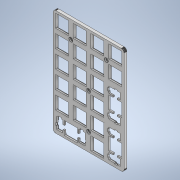
# Autodesk Inventor part: Numpad plate v1
Saved by Autodesk Inventor 2022.5 (Build 265521000, 521)
## iProperties
Created: 2024-05-07
Part Number: Numpad plate v1
Material: Generic
Document SubType Name: Modeling
Designer: OsterhaudtM
Density: 1 g/cm^3
Appearance: Default
Autodesk Inventor part; units mm, degrees
(part 1 of 2)
ref_plane "YZ Plane" through (0, 0, 0) normal (1, 0, 0) x (0, 1, 0)
ref_plane "XZ Plane" through (0, 0, 0) normal (0, 1, 0) x (-1, 0, 0)
ref_plane "XY Plane" through (0, 0, 0) normal (0, 0, 1) x (1, 0, 0)
sketch "Sketch1" plane through (0, 0, 0) normal (0, 0, 1) x (1, 0, 0)
  point P0 (0, 0)
sketch "0" plane through (0, 0, 0) normal (0, 0, 1) x (1, 0, 0)
  line L0 (73.2966, 114.558) -> (73.5323, 114.548)
  line L1 (73.5323, 114.548) -> (73.7651, 114.522)
  line L2 (73.7651, 114.522) -> (73.9965, 114.475)
  line L3 (73.9965, 114.475) -> (74.2237, 114.411)
  line L4 (74.2237, 114.411) -> (74.4442, 114.329)
  line L5 (74.4442, 114.329) -> (74.658, 114.231)
  line L6 (74.658, 114.231) -> (74.8633, 114.115)
  line L7 (74.8633, 114.115) -> (75.0591, 113.986)
  line L8 (75.0591, 113.986) -> (75.245, 113.84)
  line L9 (75.245, 113.84) -> (75.4172, 113.68)
  line L10 (75.4172, 113.68) -> (75.577, 113.506)
  line L11 (75.577, 113.506) -> (75.723, 113.322)
  line L12 (75.723, 113.322) -> (75.8543, 113.126)
  line L13 (75.8543, 113.126) -> (75.97, 112.919)
  line L14 (75.97, 112.919) -> (76.0677, 112.705)
  line L15 (76.0677, 112.705) -> (76.1488, 112.485)
  line L16 (76.1488, 112.485) -> (76.2138, 112.258)
  line L17 (76.2138, 112.258) -> (76.2593, 112.028)
  line L18 (76.2593, 112.028) -> (76.2868, 111.794)
  line L19 (76.2868, 111.794) -> (76.2963, 111.558)
  line L20 (76.2963, 111.558) -> (76.2963, 3.2563)
  line L21 (76.2963, 3.2563) -> (76.2868, 3.0207)
  line L22 (76.2868, 3.0207) -> (76.2593, 2.7878)
  line L23 (76.2593, 2.7878) -> (76.2138, 2.5563)
  line L24 (76.2138, 2.5563) -> (76.1488, 2.3289)
  line L25 (76.1488, 2.3289) -> (76.0677, 2.1084)
  line L26 (76.0677, 2.1084) -> (75.97, 1.8948)
  line L27 (75.97, 1.8948) -> (75.8543, 1.6895)
  line L28 (75.8543, 1.6895) -> (75.723, 1.4938)
  line L29 (75.723, 1.4938) -> (75.577, 1.3078)
  line L30 (75.577, 1.3078) -> (75.4172, 1.1355)
  line L31 (75.4172, 1.1355) -> (75.245, 0.9757)
  line L32 (75.245, 0.9757) -> (75.0591, 0.8296)
  line L33 (75.0591, 0.8296) -> (74.8633, 0.6987)
  line L34 (74.8633, 0.6987) -> (74.658, 0.5829)
  line L35 (74.658, 0.5829) -> (74.4442, 0.4851)
  line L36 (74.4442, 0.4851) -> (74.2237, 0.4038)
  line L37 (74.2237, 0.4038) -> (73.9965, 0.339)
  line L38 (73.9965, 0.339) -> (73.7651, 0.2935)
  line L39 (73.7651, 0.2935) -> (73.5323, 0.266)
  line L40 (73.5323, 0.266) -> (73.2952, 0.2563)
  line L41 (73.2952, 0.2563) -> (3.0951, 0.2563)
  line L42 (3.0951, 0.2563) -> (2.8594, 0.266)
  line L43 (2.8594, 0.266) -> (2.6252, 0.2935)
  line L44 (2.6252, 0.2935) -> (2.395, 0.339)
  line L45 (2.395, 0.339) -> (2.1677, 0.4038)
  line L46 (2.1677, 0.4038) -> (1.9472, 0.4851)
  line L47 (1.9472, 0.4851) -> (1.7336, 0.5829)
  line L48 (1.7336, 0.5829) -> (1.5269, 0.6987)
  line L49 (1.5269, 0.6987) -> (1.3312, 0.8296)
  line L50 (1.3312, 0.8296) -> (1.1465, 0.9757)
  line L51 (1.1465, 0.9757) -> (0.9729, 1.1355)
  line L52 (0.9729, 1.1355) -> (0.813, 1.3078)
  line L53 (0.813, 1.3078) -> (0.667, 1.4938)
  line L54 (0.667, 1.4938) -> (0.5374, 1.6895)
  line L55 (0.5374, 1.6895) -> (0.4217, 1.8948)
  line L56 (0.4217, 1.8948) -> (0.3238, 2.1084)
  line L57 (0.3238, 2.1084) -> (0.2412, 2.3289)
  line L58 (0.2412, 2.3289) -> (0.1778, 2.5563)
  line L59 (0.1778, 2.5563) -> (0.1309, 2.7878)
  line L60 (0.1309, 2.7878) -> (0.1047, 3.0207)
  line L61 (0.1047, 3.0207) -> (0.0951, 3.2577)
  line L62 (0.0951, 3.2577) -> (0.0951, 111.558)
  line L63 (0.0951, 111.558) -> (0.1047, 111.794)
  line L64 (0.1047, 111.794) -> (0.1309, 112.028)
  line L65 (0.1309, 112.028) -> (0.1778, 112.258)
  line L66 (0.1778, 112.258) -> (0.2412, 112.485)
  line L67 (0.2412, 112.485) -> (0.3238, 112.705)
  line L68 (0.3238, 112.705) -> (0.4217, 112.919)
  line L69 (0.4217, 112.919) -> (0.5374, 113.126)
  line L70 (0.5374, 113.126) -> (0.667, 113.322)
  line L71 (0.667, 113.322) -> (0.813, 113.506)
  line L72 (0.813, 113.506) -> (0.9729, 113.68)
  line L73 (0.9729, 113.68) -> (1.1465, 113.84)
  line L74 (1.1465, 113.84) -> (1.3312, 113.986)
  line L75 (1.3312, 113.986) -> (1.5269, 114.115)
  line L76 (1.5269, 114.115) -> (1.7336, 114.231)
  line L77 (1.7336, 114.231) -> (1.9472, 114.329)
  line L78 (1.9472, 114.329) -> (2.1677, 114.411)
  line L79 (2.1677, 114.411) -> (2.395, 114.475)
  line L80 (2.395, 114.475) -> (2.6252, 114.522)
  line L81 (2.6252, 114.522) -> (2.8594, 114.548)
  line L82 (2.8594, 114.548) -> (3.0951, 114.558)
  line L83 (3.0951, 114.558) -> (73.2966, 114.558)
  line L84 (12.146, 16.7831) -> (12.146, 12.0826)
  line L85 (12.146, 12.0826) -> (10.6206, 12.0826)
  line L86 (10.6206, 12.0826) -> (10.6206, 15.3128)
  line L87 (10.6206, 15.3128) -> (3.8709, 15.3128)
  line L88 (3.8709, 15.3128) -> (3.8709, 12.0826)
  line L89 (3.8709, 12.0826) -> (3.0441, 12.0826)
  line L90 (3.0441, 12.0826) -> (3.0441, 9.2838)
  line L91 (3.0441, 9.2838) -> (3.8709, 9.2838)
  line L92 (3.8709, 9.2838) -> (3.8709, 3.0138)
  line L93 (3.8709, 3.0138) -> (5.5948, 3.0138)
  line L94 (5.5948, 3.0138) -> (5.5948, 1.8135)
  line L95 (5.5948, 1.8135) -> (8.8952, 1.8135)
  line L96 (8.8952, 1.8135) -> (8.8952, 3.0138)
  line L97 (8.8952, 3.0138) -> (10.6206, 3.0138)
  line L98 (10.6206, 3.0138) -> (10.6206, 7.4827)
  line L99 (10.6206, 7.4827) -> (12.146, 7.4827)
  line L100 (12.146, 7.4827) -> (12.146, 2.7836)
  line L101 (12.146, 2.7836) -> (26.1455, 2.7836)
  line L102 (26.1455, 2.7836) -> (26.1455, 7.4827)
  line L103 (26.1455, 7.4827) -> (27.671, 7.4827)
  line L104 (27.671, 7.4827) -> (27.671, 3.0138)
  line L105 (27.671, 3.0138) -> (29.3949, 3.0138)
  line L106 (29.3949, 3.0138) -> (29.3949, 1.8135)
  line L107 (29.3949, 1.8135) -> (32.6953, 1.8135)
  line L108 (32.6953, 1.8135) -> (32.6953, 3.0138)
  line L109 (32.6953, 3.0138) -> (34.4206, 3.0138)
  line L110 (34.4206, 3.0138) -> (34.4206, 9.2838)
  line L111 (34.4206, 9.2838) -> (35.2461, 9.2838)
  line L112 (35.2461, 9.2838) -> (35.2461, 12.0826)
  line L113 (35.2461, 12.0826) -> (34.4206, 12.0826)
  line L114 (34.4206, 12.0826) -> (34.4206, 15.3128)
  line L115 (34.4206, 15.3128) -> (27.671, 15.3128)
  line L116 (27.671, 15.3128) -> (27.671, 12.0826)
  line L117 (27.671, 12.0826) -> (26.1455, 12.0826)
  line L118 (26.1455, 12.0826) -> (26.1455, 16.7831)
  line L119 (26.1455, 16.7831) -> (12.146, 16.7831)
  line L120 (40.7211, 16.7831) -> (54.7204, 16.7831)
  line L121 (54.7204, 16.7831) -> (54.7204, 2.7836)
  line L122 (54.7204, 2.7836) -> (40.7211, 2.7836)
  line L123 (40.7211, 2.7836) -> (40.7211, 16.7831)
  line L124 (66.27, 35.4072) -> (66.27, 34.5819)
  line L125 (66.27, 34.5819) -> (60.0012, 34.5819)
  line L126 (60.0012, 34.5819) -> (60.0012, 32.8579)
  line L127 (60.0012, 32.8579) -> (58.801, 32.8579)
  line L128 (58.801, 32.8579) -> (58.801, 29.5576)
  line L129 (58.801, 29.5576) -> (60.0012, 29.5576)
  line L130 (60.0012, 29.5576) -> (60.0012, 27.8322)
  line L131 (60.0012, 27.8322) -> (64.4701, 27.8322)
  line L132 (64.4701, 27.8322) -> (64.4701, 26.3067)
  line L133 (64.4701, 26.3067) -> (59.7711, 26.3067)
  line L134 (59.7711, 26.3067) -> (59.7711, 12.3073)
  line L135 (59.7711, 12.3073) -> (64.4701, 12.3073)
  line L136 (64.4701, 12.3073) -> (64.4701, 10.7818)
  line L137 (64.4701, 10.7818) -> (60.0012, 10.7818)
  line L138 (60.0012, 10.7818) -> (60.0012, 9.0579)
  line L139 (60.0012, 9.0579) -> (58.801, 9.0579)
  line L140 (58.801, 9.0579) -> (58.801, 5.7574)
  line L141 (58.801, 5.7574) -> (60.0012, 5.7574)
  line L142 (60.0012, 5.7574) -> (60.0012, 4.0321)
  line L143 (60.0012, 4.0321) -> (66.27, 4.0321)
  line L144 (66.27, 4.0321) -> (66.27, 3.2067)
  line L145 (66.27, 3.2067) -> (69.07, 3.2067)
  line L146 (69.07, 3.2067) -> (69.07, 4.0321)
  line L147 (69.07, 4.0321) -> (72.3, 4.0321)
  line L148 (72.3, 4.0321) -> (72.3, 10.7818)
  line L149 (72.3, 10.7818) -> (69.07, 10.7818)
  line L150 (69.07, 10.7818) -> (69.07, 12.3073)
  line L151 (69.07, 12.3073) -> (73.7704, 12.3073)
  line L152 (73.7704, 12.3073) -> (73.7704, 26.3067)
  line L153 (73.7704, 26.3067) -> (69.07, 26.3067)
  line L154 (69.07, 26.3067) -> (69.07, 27.8322)
  line L155 (69.07, 27.8322) -> (72.3, 27.8322)
  line L156 (72.3, 27.8322) -> (72.3, 34.5819)
  line L157 (72.3, 34.5819) -> (69.07, 34.5819)
  line L158 (69.07, 34.5819) -> (69.07, 35.4072)
  line L159 (69.07, 35.4072) -> (66.27, 35.4072)
  line L160 (2.621, 35.8316) -> (16.6205, 35.8316)
  line L161 (16.6205, 35.8316) -> (16.6205, 21.8323)
  line L162 (16.6205, 21.8323) -> (2.621, 21.8323)
  line L163 (2.621, 21.8323) -> (2.621, 35.8316)
  line L164 (21.671, 35.8316) -> (35.6704, 35.8316)
  line L165 (35.6704, 35.8316) -> (35.6704, 21.8323)
  line L166 (35.6704, 21.8323) -> (21.671, 21.8323)
  line L167 (21.671, 21.8323) -> (21.671, 35.8316)
  line L168 (40.7211, 35.8316) -> (54.7204, 35.8316)
  line L169 (54.7204, 35.8316) -> (54.7204, 21.8323)
  line L170 (54.7204, 21.8323) -> (40.7211, 21.8323)
  line L171 (40.7211, 21.8323) -> (40.7211, 35.8316)
  line L172 (2.621, 54.8816) -> (16.6205, 54.8816)
  line L173 (16.6205, 54.8816) -> (16.6205, 40.8824)
  line L174 (16.6205, 40.8824) -> (2.621, 40.8824)
  line L175 (2.621, 40.8824) -> (2.621, 54.8816)
  line L176 (21.671, 54.8816) -> (35.6704, 54.8816)
  line L177 (35.6704, 54.8816) -> (35.6704, 40.8824)
  line L178 (35.6704, 40.8824) -> (21.671, 40.8824)
  line L179 (21.671, 40.8824) -> (21.671, 54.8816)
  line L180 (40.7211, 54.8816) -> (54.7204, 54.8816)
  line L181 (54.7204, 54.8816) -> (54.7204, 40.8824)
  line L182 (54.7204, 40.8824) -> (40.7211, 40.8824)
  line L183 (40.7211, 40.8824) -> (40.7211, 54.8816)
  line L184 (66.27, 73.5072) -> (66.27, 72.6817)
  line L185 (66.27, 72.6817) -> (60.0012, 72.6817)
  line L186 (60.0012, 72.6817) -> (60.0012, 70.9581)
  line L187 (60.0012, 70.9581) -> (58.801, 70.9581)
  line L188 (58.801, 70.9581) -> (58.801, 67.6575)
  line L189 (58.801, 67.6575) -> (60.0012, 67.6575)
  line L190 (60.0012, 67.6575) -> (60.0012, 65.9324)
  line L191 (60.0012, 65.9324) -> (64.4701, 65.9324)
  line L192 (64.4701, 65.9324) -> (64.4701, 64.4066)
  line L193 (64.4701, 64.4066) -> (59.7711, 64.4066)
  line L194 (59.7711, 64.4066) -> (59.7711, 50.4074)
  line L195 (59.7711, 50.4074) -> (64.4701, 50.4074)
  line L196 (64.4701, 50.4074) -> (64.4701, 48.8819)
  line L197 (64.4701, 48.8819) -> (60.0012, 48.8819)
  line L198 (60.0012, 48.8819) -> (60.0012, 47.1579)
  line L199 (60.0012, 47.1579) -> (58.801, 47.1579)
  line L200 (58.801, 47.1579) -> (58.801, 43.8573)
  line L201 (58.801, 43.8573) -> (60.0012, 43.8573)
  line L202 (60.0012, 43.8573) -> (60.0012, 42.1323)
  line L203 (60.0012, 42.1323) -> (66.27, 42.1323)
  line L204 (66.27, 42.1323) -> (66.27, 41.3067)
  line L205 (66.27, 41.3067) -> (69.07, 41.3067)
  line L206 (69.07, 41.3067) -> (69.07, 42.1323)
  line L207 (69.07, 42.1323) -> (72.3, 42.1323)
  line L208 (72.3, 42.1323) -> (72.3, 48.8819)
  line L209 (72.3, 48.8819) -> (69.07, 48.8819)
  line L210 (69.07, 48.8819) -> (69.07, 50.4074)
  line L211 (69.07, 50.4074) -> (73.7704, 50.4074)
  line L212 (73.7704, 50.4074) -> (73.7704, 64.4066)
  line L213 (73.7704, 64.4066) -> (69.07, 64.4066)
  line L214 (69.07, 64.4066) -> (69.07, 65.9324)
  line L215 (69.07, 65.9324) -> (72.3, 65.9324)
  line L216 (72.3, 65.9324) -> (72.3, 72.6817)
  line L217 (72.3, 72.6817) -> (69.07, 72.6817)
  line L218 (69.07, 72.6817) -> (69.07, 73.5072)
  line L219 (69.07, 73.5072) -> (66.27, 73.5072)
  line L220 (2.621, 73.9316) -> (16.6205, 73.9316)
  line L221 (16.6205, 73.9316) -> (16.6205, 59.9324)
  line L222 (16.6205, 59.9324) -> (2.621, 59.9324)
  line L223 (2.621, 59.9324) -> (2.621, 73.9316)
  line L224 (21.671, 73.9316) -> (35.6704, 73.9316)
  line L225 (35.6704, 73.9316) -> (35.6704, 59.9324)
  line L226 (35.6704, 59.9324) -> (21.671, 59.9324)
  line L227 (21.671, 59.9324) -> (21.671, 73.9316)
  line L228 (40.7211, 73.9316) -> (54.7204, 73.9316)
  line L229 (54.7204, 73.9316) -> (54.7204, 59.9324)
  line L230 (54.7204, 59.9324) -> (40.7211, 59.9324)
  line L231 (40.7211, 59.9324) -> (40.7211, 73.9316)
  line L232 (2.621, 92.9816) -> (16.6205, 92.9816)
  line L233 (16.6205, 92.9816) -> (16.6205, 78.9824)
  line L234 (16.6205, 78.9824) -> (2.621, 78.9824)
  line L235 (2.621, 78.9824) -> (2.621, 92.9816)
  line L236 (21.671, 92.9816) -> (35.6704, 92.9816)
  line L237 (35.6704, 92.9816) -> (35.6704, 78.9824)
  line L238 (35.6704, 78.9824) -> (21.671, 78.9824)
  line L239 (21.671, 78.9824) -> (21.671, 92.9816)
  line L240 (40.7211, 92.9816) -> (54.7204, 92.9816)
  line L241 (54.7204, 92.9816) -> (54.7204, 78.9824)
  line L242 (54.7204, 78.9824) -> (40.7211, 78.9824)
  line L243 (40.7211, 78.9824) -> (40.7211, 92.9816)
  line L244 (59.7711, 92.9816) -> (73.7704, 92.9816)
  line L245 (73.7704, 92.9816) -> (73.7704, 78.9824)
  line L246 (73.7704, 78.9824) -> (59.7711, 78.9824)
  line L247 (59.7711, 78.9824) -> (59.7711, 92.9816)
  line L248 (2.621, 112.032) -> (16.6205, 112.032)
  line L249 (16.6205, 112.032) -> (16.6205, 98.0324)
  line L250 (16.6205, 98.0324) -> (2.621, 98.0324)
  line L251 (2.621, 98.0324) -> (2.621, 112.032)
  line L252 (21.671, 112.032) -> (35.6704, 112.032)
  line L253 (35.6704, 112.032) -> (35.6704, 98.0324)
  line L254 (35.6704, 98.0324) -> (21.671, 98.0324)
  line L255 (21.671, 98.0324) -> (21.671, 112.032)
  line L256 (40.7211, 112.032) -> (54.7204, 112.032)
  line L257 (54.7204, 112.032) -> (54.7204, 98.0324)
  line L258 (54.7204, 98.0324) -> (40.7211, 98.0324)
  line L259 (40.7211, 98.0324) -> (40.7211, 112.032)
  line L260 (59.7711, 112.032) -> (73.7704, 112.032)
  line L261 (73.7704, 112.032) -> (73.7704, 98.0324)
  line L262 (73.7704, 98.0324) -> (59.7711, 98.0324)
  line L263 (59.7711, 98.0324) -> (59.7711, 112.032)
  line L264 (19.1457, 16.7831) -> (19.1457, 2.7836) construction
  line L265 (19.1457, 9.7834) -> (24.0162, 9.7834) construction
  line L266 (12.146, 2.7836) -> (12.146, 7.4841)
  line L267 (12.146, 7.4841) -> (10.6206, 7.4841)
  line L268 (10.6206, 7.4841) -> (10.6206, 4.2539)
  line L269 (10.6206, 4.2539) -> (3.8709, 4.2539)
  line L270 (3.8709, 4.2539) -> (3.8709, 7.4841)
  line L271 (3.8709, 7.4841) -> (3.0441, 7.4841)
  line L272 (3.0441, 7.4841) -> (3.0441, 10.2829)
  line L273 (3.0441, 10.2829) -> (3.8709, 10.2829)
  line L274 (3.8709, 10.2829) -> (3.8709, 16.553)
  line L275 (3.8709, 16.553) -> (5.5948, 16.553)
  line L276 (5.5948, 16.553) -> (5.5948, 17.7532)
  line L277 (5.5948, 17.7532) -> (8.8952, 17.7532)
  line L278 (8.8952, 17.7532) -> (8.8952, 16.553)
  line L279 (8.8952, 16.553) -> (10.6206, 16.553)
  line L280 (10.6206, 16.553) -> (10.6206, 12.084)
  line L281 (10.6206, 12.084) -> (12.146, 12.084)
  line L282 (12.146, 12.084) -> (12.146, 16.7831)
  line L283 (12.146, 16.7831) -> (26.1455, 16.7831)
  line L284 (26.1455, 16.7831) -> (26.1455, 12.084)
  line L285 (26.1455, 12.084) -> (27.671, 12.084)
  line L286 (27.671, 12.084) -> (27.671, 16.553)
  line L287 (27.671, 16.553) -> (29.3949, 16.553)
  line L288 (29.3949, 16.553) -> (29.3949, 17.7532)
  line L289 (29.3949, 17.7532) -> (32.6953, 17.7532)
  line L290 (32.6953, 17.7532) -> (32.6953, 16.553)
  line L291 (32.6953, 16.553) -> (34.4206, 16.553)
  line L292 (34.4206, 16.553) -> (34.4206, 10.2829)
  line L293 (34.4206, 10.2829) -> (35.2461, 10.2829)
  line L294 (35.2461, 10.2829) -> (35.2461, 7.4841)
  line L295 (35.2461, 7.4841) -> (34.4206, 7.4841)
  line L296 (34.4206, 7.4841) -> (34.4206, 4.2539)
  line L297 (34.4206, 4.2539) -> (27.671, 4.2539)
  line L298 (27.671, 4.2539) -> (27.671, 7.4841)
  line L299 (27.671, 7.4841) -> (26.1455, 7.4841)
  line L300 (26.1455, 7.4841) -> (26.1455, 2.7836)
  line L301 (26.1455, 2.7836) -> (12.146, 2.7836)
  line L302 (19.1457, 2.7836) -> (19.1457, 16.7831) construction
  point P0 (3.0951, 0.2563)
  point P1 (76.2963, 3.2563)
  point P2 (54.7204, 2.7836)
  constraints: 606 end point, 74 symmetric about line, 3 midpoint, 1 horizontal
extrude "Extrusion1" add sketch "0" along normal blind 3 contours L0 L1 L2 L3 L4 L5 L6 L7 L8 L9 L10 L11 L12 L13 L14 L15 L16 L17 L18 L19 L20 L21 L22 L23 L24 L25 L26 L27 L28 L29 L30 L31 L32 L33 L34 L35 L36 L37 L38 L39 L40 L41 L42 L43 L44 L45 L46 L47 L48 L49 L50 L51 L52 L53 L54 L55 L56 L57 L58 L59 L60 L61 L62 L63 L64 L65 L66 L67 L68 L69 L70 L71 L72 L73 L74 L75 L76 L77 L78 L79 L80 L81 L82 L83 | L274 L273 L90 L89 | L113 L112 L293 L292 | L269 L98 L97 L96 L95 L94 L93 L92 | L110 L109 L108 L107 L106 L105 L104 L297
sketch "Sketch3" plane through (0, 0, 0) normal (0, 0, -1) x (-1, 0, 0)
  line L0 (0, 0) -> (-38.1, 0)
  line L1 (-38.1, 0) -> (-38.1, 19.6873)
  line L2 (-38.1, 19.6873) -> (0, 19.6873)
  line L3 (0, 19.6873) -> (0, 0)
  line L4 (-76.2963, 0.2563) -> (-56.8653, 0.2563)
  line L5 (-56.8653, 0.2563) -> (-56.8653, 76.4563)
  line L6 (-56.8653, 76.4563) -> (-76.2963, 76.4563)
  line L7 (-76.2963, 76.4563) -> (-76.2963, 0.2563)
  line L8 (-3.0951, 114.558) -> (-2.8594, 114.548) projected
  line L9 (-73.2966, 114.558) -> (-3.0951, 114.558) projected
  line L10 (-73.5323, 114.548) -> (-73.2966, 114.558) projected
  line L11 (-73.7651, 114.522) -> (-73.5323, 114.548) projected
  line L12 (-73.9965, 114.475) -> (-73.7651, 114.522) projected
  line L13 (-74.2237, 114.411) -> (-73.9965, 114.475) projected
  line L14 (-74.4442, 114.329) -> (-74.2237, 114.411) projected
  line L15 (-74.658, 114.231) -> (-74.4442, 114.329) projected
  line L16 (-74.8633, 114.115) -> (-74.658, 114.231) projected
  line L17 (-75.0591, 113.986) -> (-74.8633, 114.115) projected
  line L18 (-75.245, 113.84) -> (-75.0591, 113.986) projected
  line L19 (-75.4172, 113.68) -> (-75.245, 113.84) projected
  line L20 (-75.577, 113.506) -> (-75.4172, 113.68) projected
  line L21 (-75.723, 113.322) -> (-75.577, 113.506) projected
  line L22 (-75.8543, 113.126) -> (-75.723, 113.322) projected
  line L23 (-75.97, 112.919) -> (-75.8543, 113.126) projected
  line L24 (-76.0677, 112.705) -> (-75.97, 112.919) projected
  line L25 (-76.1488, 112.485) -> (-76.0677, 112.705) projected
  line L26 (-76.2138, 112.258) -> (-76.1488, 112.485) projected
  line L27 (-76.2593, 112.028) -> (-76.2138, 112.258) projected
  line L28 (-76.2868, 111.794) -> (-76.2593, 112.028) projected
  line L29 (-76.2963, 111.558) -> (-76.2868, 111.794) projected
  line L30 (-76.2963, 3.2563) -> (-76.2963, 111.558) projected
  line L31 (-76.2868, 3.0207) -> (-76.2963, 3.2563) projected
  line L32 (-76.2593, 2.7878) -> (-76.2868, 3.0207) projected
  line L33 (-76.2138, 2.5563) -> (-76.2593, 2.7878) projected
  line L34 (-76.1488, 2.3289) -> (-76.2138, 2.5563) projected
  line L35 (-76.0677, 2.1084) -> (-76.1488, 2.3289) projected
  line L36 (-75.97, 1.8948) -> (-76.0677, 2.1084) projected
  line L37 (-75.8543, 1.6895) -> (-75.97, 1.8948) projected
  line L38 (-75.723, 1.4938) -> (-75.8543, 1.6895) projected
  line L39 (-75.577, 1.3078) -> (-75.723, 1.4938) projected
  line L40 (-75.4172, 1.1355) -> (-75.577, 1.3078) projected
  line L41 (-75.245, 0.9757) -> (-75.4172, 1.1355) projected
  line L42 (-75.0591, 0.8296) -> (-75.245, 0.9757) projected
  line L43 (-74.8633, 0.6987) -> (-75.0591, 0.8296) projected
  line L44 (-74.658, 0.5829) -> (-74.8633, 0.6987) projected
  line L45 (-74.4442, 0.4851) -> (-74.658, 0.5829) projected
  line L46 (-74.2237, 0.4038) -> (-74.4442, 0.4851) projected
  line L47 (-73.9965, 0.339) -> (-74.2237, 0.4038) projected
  line L48 (-73.7651, 0.2935) -> (-73.9965, 0.339) projected
  line L49 (-73.5323, 0.266) -> (-73.7651, 0.2935) projected
  line L50 (-73.2952, 0.2563) -> (-73.5323, 0.266) projected
  line L51 (-3.0951, 0.2563) -> (-73.2952, 0.2563) projected
  line L52 (-2.8594, 0.266) -> (-3.0951, 0.2563) projected
  line L53 (-2.6252, 0.2935) -> (-2.8594, 0.266) projected
  line L54 (-2.395, 0.339) -> (-2.6252, 0.2935) projected
  line L55 (-2.1677, 0.4038) -> (-2.395, 0.339) projected
  line L56 (-1.9472, 0.4851) -> (-2.1677, 0.4038) projected
  line L57 (-1.7336, 0.5829) -> (-1.9472, 0.4851) projected
  line L58 (-1.5269, 0.6987) -> (-1.7336, 0.5829) projected
  line L59 (-1.3312, 0.8296) -> (-1.5269, 0.6987) projected
  line L60 (-1.1465, 0.9757) -> (-1.3312, 0.8296) projected
  line L61 (-0.9729, 1.1355) -> (-1.1465, 0.9757) projected
  line L62 (-0.813, 1.3078) -> (-0.9729, 1.1355) projected
  line L63 (-0.667, 1.4938) -> (-0.813, 1.3078) projected
  line L64 (-0.5374, 1.6895) -> (-0.667, 1.4938) projected
  line L65 (-0.4217, 1.8948) -> (-0.5374, 1.6895) projected
  line L66 (-0.3238, 2.1084) -> (-0.4217, 1.8948) projected
  line L67 (-0.2412, 2.3289) -> (-0.3238, 2.1084) projected
  line L68 (-0.1778, 2.5563) -> (-0.2412, 2.3289) projected
  line L69 (-0.1309, 2.7878) -> (-0.1778, 2.5563) projected
  line L70 (-0.1047, 3.0207) -> (-0.1309, 2.7878) projected
  line L71 (-0.0951, 3.2577) -> (-0.1047, 3.0207) projected
  line L72 (-0.0951, 111.558) -> (-0.0951, 3.2577) projected
  line L73 (-0.1047, 111.794) -> (-0.0951, 111.558) projected
  line L74 (-0.1309, 112.028) -> (-0.1047, 111.794) projected
  line L75 (-0.1778, 112.258) -> (-0.1309, 112.028) projected
  line L76 (-0.2412, 112.485) -> (-0.1778, 112.258) projected
  line L77 (-0.3238, 112.705) -> (-0.2412, 112.485) projected
  line L78 (-0.4217, 112.919) -> (-0.3238, 112.705) projected
  line L79 (-0.5374, 113.126) -> (-0.4217, 112.919) projected
  line L80 (-0.667, 113.322) -> (-0.5374, 113.126) projected
  line L81 (-0.813, 113.506) -> (-0.667, 113.322) projected
  line L82 (-0.9729, 113.68) -> (-0.813, 113.506) projected
  line L83 (-1.1465, 113.84) -> (-0.9729, 113.68) projected
  line L84 (-1.3312, 113.986) -> (-1.1465, 113.84) projected
  line L85 (-1.5269, 114.115) -> (-1.3312, 113.986) projected
  line L86 (-1.7336, 114.231) -> (-1.5269, 114.115) projected
  line L87 (-1.9472, 114.329) -> (-1.7336, 114.231) projected
  line L88 (-2.1677, 114.411) -> (-1.9472, 114.329) projected
  line L89 (-2.395, 114.475) -> (-2.1677, 114.411) projected
  line L90 (-2.6252, 114.522) -> (-2.395, 114.475) projected
  line L91 (-2.8594, 114.548) -> (-2.6252, 114.522) projected
  line L92 (-59.7711, 112.032) -> (-73.7704, 112.032) projected
  line L93 (-59.7711, 98.0324) -> (-59.7711, 112.032) projected
  line L94 (-73.7704, 98.0324) -> (-59.7711, 98.0324) projected
  line L95 (-73.7704, 112.032) -> (-73.7704, 98.0324) projected
  line L96 (-40.7211, 112.032) -> (-54.7204, 112.032) projected
  line L97 (-40.7211, 98.0324) -> (-40.7211, 112.032) projected
  line L98 (-54.7204, 98.0324) -> (-40.7211, 98.0324) projected
  line L99 (-54.7204, 112.032) -> (-54.7204, 98.0324) projected
  line L100 (-21.671, 112.032) -> (-35.6704, 112.032) projected
  line L101 (-21.671, 98.0324) -> (-21.671, 112.032) projected
  line L102 (-35.6704, 98.0324) -> (-21.671, 98.0324) projected
  line L103 (-35.6704, 112.032) -> (-35.6704, 98.0324) projected
  line L104 (-2.621, 112.032) -> (-16.6205, 112.032) projected
  line L105 (-2.621, 98.0324) -> (-2.621, 112.032) projected
  line L106 (-16.6205, 98.0324) -> (-2.621, 98.0324) projected
  line L107 (-16.6205, 112.032) -> (-16.6205, 98.0324) projected
  line L108 (-59.7711, 92.9816) -> (-73.7704, 92.9816) projected
  line L109 (-59.7711, 78.9824) -> (-59.7711, 92.9816) projected
  line L110 (-73.7704, 78.9824) -> (-59.7711, 78.9824) projected
  line L111 (-73.7704, 92.9816) -> (-73.7704, 78.9824) projected
  line L112 (-40.7211, 92.9816) -> (-54.7204, 92.9816) projected
  line L113 (-40.7211, 78.9824) -> (-40.7211, 92.9816) projected
  line L114 (-54.7204, 78.9824) -> (-40.7211, 78.9824) projected
  line L115 (-54.7204, 92.9816) -> (-54.7204, 78.9824) projected
  line L116 (-21.671, 92.9816) -> (-35.6704, 92.9816) projected
  line L117 (-21.671, 78.9824) -> (-21.671, 92.9816) projected
  line L118 (-35.6704, 78.9824) -> (-21.671, 78.9824) projected
  line L119 (-35.6704, 92.9816) -> (-35.6704, 78.9824) projected
  line L120 (-2.621, 92.9816) -> (-16.6205, 92.9816) projected
  line L121 (-2.621, 78.9824) -> (-2.621, 92.9816) projected
  line L122 (-16.6205, 78.9824) -> (-2.621, 78.9824) projected
  line L123 (-16.6205, 92.9816) -> (-16.6205, 78.9824) projected
  line L124 (-40.7211, 73.9316) -> (-54.7204, 73.9316) projected
  line L125 (-40.7211, 59.9324) -> (-40.7211, 73.9316) projected
  line L126 (-54.7204, 59.9324) -> (-40.7211, 59.9324) projected
  line L127 (-54.7204, 73.9316) -> (-54.7204, 59.9324) projected
  line L128 (-21.671, 73.9316) -> (-35.6704, 73.9316) projected
  line L129 (-21.671, 59.9324) -> (-21.671, 73.9316) projected
  line L130 (-35.6704, 59.9324) -> (-21.671, 59.9324) projected
  line L131 (-35.6704, 73.9316) -> (-35.6704, 59.9324) projected
  line L132 (-2.621, 73.9316) -> (-16.6205, 73.9316) projected
  line L133 (-2.621, 59.9324) -> (-2.621, 73.9316) projected
  line L134 (-16.6205, 59.9324) -> (-2.621, 59.9324) projected
  line L135 (-16.6205, 73.9316) -> (-16.6205, 59.9324) projected
  line L136 (-66.27, 73.5072) -> (-69.07, 73.5072) projected
  line L137 (-66.27, 72.6817) -> (-66.27, 73.5072) projected
  line L138 (-60.0012, 72.6817) -> (-66.27, 72.6817) projected
  line L139 (-60.0012, 70.9581) -> (-60.0012, 72.6817) projected
  line L140 (-58.801, 70.9581) -> (-60.0012, 70.9581) projected
  line L141 (-58.801, 67.6575) -> (-58.801, 70.9581) projected
  line L142 (-60.0012, 67.6575) -> (-58.801, 67.6575) projected
  line L143 (-60.0012, 65.9324) -> (-60.0012, 67.6575) projected
  line L144 (-64.4701, 65.9324) -> (-60.0012, 65.9324) projected
  line L145 (-64.4701, 64.4066) -> (-64.4701, 65.9324) projected
  line L146 (-59.7711, 64.4066) -> (-64.4701, 64.4066) projected
  line L147 (-59.7711, 50.4074) -> (-59.7711, 64.4066) projected
  line L148 (-64.4701, 50.4074) -> (-59.7711, 50.4074) projected
  line L149 (-64.4701, 48.8819) -> (-64.4701, 50.4074) projected
  line L150 (-60.0012, 48.8819) -> (-64.4701, 48.8819) projected
  line L151 (-60.0012, 47.1579) -> (-60.0012, 48.8819) projected
  line L152 (-58.801, 47.1579) -> (-60.0012, 47.1579) projected
  line L153 (-58.801, 43.8573) -> (-58.801, 47.1579) projected
  line L154 (-60.0012, 43.8573) -> (-58.801, 43.8573) projected
  line L155 (-60.0012, 42.1323) -> (-60.0012, 43.8573) projected
  line L156 (-66.27, 42.1323) -> (-60.0012, 42.1323) projected
  line L157 (-66.27, 41.3067) -> (-66.27, 42.1323) projected
  line L158 (-69.07, 41.3067) -> (-66.27, 41.3067) projected
  line L159 (-69.07, 42.1323) -> (-69.07, 41.3067) projected
  line L160 (-72.3, 42.1323) -> (-69.07, 42.1323) projected
  line L161 (-72.3, 48.8819) -> (-72.3, 42.1323) projected
  line L162 (-69.07, 48.8819) -> (-72.3, 48.8819) projected
  line L163 (-69.07, 50.4074) -> (-69.07, 48.8819) projected
  line L164 (-73.7704, 50.4074) -> (-69.07, 50.4074) projected
  line L165 (-73.7704, 64.4066) -> (-73.7704, 50.4074) projected
  line L166 (-69.07, 64.4066) -> (-73.7704, 64.4066) projected
  line L167 (-69.07, 65.9324) -> (-69.07, 64.4066) projected
  line L168 (-72.3, 65.9324) -> (-69.07, 65.9324) projected
  line L169 (-72.3, 72.6817) -> (-72.3, 65.9324) projected
  line L170 (-69.07, 72.6817) -> (-72.3, 72.6817) projected
  line L171 (-69.07, 73.5072) -> (-69.07, 72.6817) projected
  line L172 (-40.7211, 54.8816) -> (-54.7204, 54.8816) projected
  line L173 (-40.7211, 40.8824) -> (-40.7211, 54.8816) projected
  line L174 (-54.7204, 40.8824) -> (-40.7211, 40.8824) projected
  line L175 (-54.7204, 54.8816) -> (-54.7204, 40.8824) projected
  line L176 (-21.671, 54.8816) -> (-35.6704, 54.8816) projected
  line L177 (-21.671, 40.8824) -> (-21.671, 54.8816) projected
  line L178 (-35.6704, 40.8824) -> (-21.671, 40.8824) projected
  line L179 (-35.6704, 54.8816) -> (-35.6704, 40.8824) projected
  line L180 (-2.621, 54.8816) -> (-16.6205, 54.8816) projected
  line L181 (-2.621, 40.8824) -> (-2.621, 54.8816) projected
  line L182 (-16.6205, 40.8824) -> (-2.621, 40.8824) projected
  line L183 (-16.6205, 54.8816) -> (-16.6205, 40.8824) projected
  line L184 (-40.7211, 35.8316) -> (-54.7204, 35.8316) projected
  line L185 (-40.7211, 21.8323) -> (-40.7211, 35.8316) projected
  line L186 (-54.7204, 21.8323) -> (-40.7211, 21.8323) projected
  line L187 (-54.7204, 35.8316) -> (-54.7204, 21.8323) projected
  line L188 (-21.671, 35.8316) -> (-35.6704, 35.8316) projected
  line L189 (-21.671, 21.8323) -> (-21.671, 35.8316) projected
  line L190 (-35.6704, 21.8323) -> (-21.671, 21.8323) projected
  line L191 (-35.6704, 35.8316) -> (-35.6704, 21.8323) projected
  line L192 (-2.621, 35.8316) -> (-16.6205, 35.8316) projected
  line L193 (-2.621, 21.8323) -> (-2.621, 35.8316) projected
  line L194 (-16.6205, 21.8323) -> (-2.621, 21.8323) projected
  line L195 (-16.6205, 35.8316) -> (-16.6205, 21.8323) projected
  line L196 (-66.27, 35.4072) -> (-69.07, 35.4072) projected
  line L197 (-66.27, 34.5819) -> (-66.27, 35.4072) projected
  line L198 (-60.0012, 34.5819) -> (-66.27, 34.5819) projected
  line L199 (-60.0012, 32.8579) -> (-60.0012, 34.5819) projected
  line L200 (-58.801, 32.8579) -> (-60.0012, 32.8579) projected
  line L201 (-58.801, 29.5576) -> (-58.801, 32.8579) projected
  line L202 (-60.0012, 29.5576) -> (-58.801, 29.5576) projected
  line L203 (-60.0012, 27.8322) -> (-60.0012, 29.5576) projected
  line L204 (-64.4701, 27.8322) -> (-60.0012, 27.8322) projected
  line L205 (-64.4701, 26.3067) -> (-64.4701, 27.8322) projected
  line L206 (-59.7711, 26.3067) -> (-64.4701, 26.3067) projected
  line L207 (-59.7711, 12.3073) -> (-59.7711, 26.3067) projected
  line L208 (-64.4701, 12.3073) -> (-59.7711, 12.3073) projected
  line L209 (-64.4701, 10.7818) -> (-64.4701, 12.3073) projected
  line L210 (-60.0012, 10.7818) -> (-64.4701, 10.7818) projected
  line L211 (-60.0012, 9.0579) -> (-60.0012, 10.7818) projected
  line L212 (-58.801, 9.0579) -> (-60.0012, 9.0579) projected
  line L213 (-58.801, 5.7574) -> (-58.801, 9.0579) projected
  line L214 (-60.0012, 5.7574) -> (-58.801, 5.7574) projected
  line L215 (-60.0012, 4.0321) -> (-60.0012, 5.7574) projected
  line L216 (-66.27, 4.0321) -> (-60.0012, 4.0321) projected
  line L217 (-66.27, 3.2067) -> (-66.27, 4.0321) projected
  line L218 (-69.07, 3.2067) -> (-66.27, 3.2067) projected
  line L219 (-69.07, 4.0321) -> (-69.07, 3.2067) projected
  line L220 (-72.3, 4.0321) -> (-69.07, 4.0321) projected
  line L221 (-72.3, 10.7818) -> (-72.3, 4.0321) projected
  line L222 (-69.07, 10.7818) -> (-72.3, 10.7818) projected
  line L223 (-69.07, 12.3073) -> (-69.07, 10.7818) projected
  line L224 (-73.7704, 12.3073) -> (-69.07, 12.3073) projected
  line L225 (-73.7704, 26.3067) -> (-73.7704, 12.3073) projected
  line L226 (-69.07, 26.3067) -> (-73.7704, 26.3067) projected
  line L227 (-69.07, 27.8322) -> (-69.07, 26.3067) projected
  line L228 (-72.3, 27.8322) -> (-69.07, 27.8322) projected
  line L229 (-72.3, 34.5819) -> (-72.3, 27.8322) projected
  line L230 (-69.07, 34.5819) -> (-72.3, 34.5819) projected
  line L231 (-69.07, 35.4072) -> (-69.07, 34.5819) projected
  line L232 (-40.7211, 16.7831) -> (-54.7204, 16.7831) projected
  line L233 (-40.7211, 2.7836) -> (-40.7211, 16.7831) projected
  line L234 (-54.7204, 2.7836) -> (-40.7211, 2.7836) projected
  line L235 (-54.7204, 16.7831) -> (-54.7204, 2.7836) projected
  line L236 (-12.146, 16.7831) -> (-26.1455, 16.7831) projected
  line L237 (-12.146, 12.0826) -> (-12.146, 16.7831) projected
  line L238 (-10.6206, 12.0826) -> (-12.146, 12.0826) projected
  line L239 (-10.6206, 16.553) -> (-10.6206, 12.0826) projected
  line L240 (-3.8709, 10.2829) -> (-3.8709, 16.553) projected
  line L241 (-3.0441, 7.4841) -> (-3.0441, 10.2829) projected
  line L242 (-3.8709, 4.2539) -> (-3.8709, 7.4841) projected
  line L243 (-10.6206, 7.4827) -> (-10.6206, 4.2539) projected
  line L244 (-12.146, 7.4827) -> (-10.6206, 7.4827) projected
  line L245 (-12.146, 2.7836) -> (-12.146, 7.4827) projected
  line L246 (-26.1455, 2.7836) -> (-12.146, 2.7836) projected
  line L247 (-26.1455, 7.4827) -> (-26.1455, 2.7836) projected
  line L248 (-27.671, 7.4827) -> (-26.1455, 7.4827) projected
  line L249 (-27.671, 4.2539) -> (-27.671, 7.4827) projected
  line L250 (-34.4206, 7.4841) -> (-34.4206, 4.2539) projected
  line L251 (-35.2461, 10.2829) -> (-35.2461, 7.4841) projected
  line L252 (-34.4206, 16.553) -> (-34.4206, 10.2829) projected
  line L253 (-27.671, 12.0826) -> (-27.671, 16.553) projected
  line L254 (-26.1455, 12.0826) -> (-27.671, 12.0826) projected
  line L255 (-26.1455, 16.7831) -> (-26.1455, 12.0826) projected
  line L256 (-10.6206, 4.2539) -> (-3.8709, 4.2539) projected
  line L257 (-34.4206, 4.2539) -> (-27.671, 4.2539) projected
  line L258 (-35.2461, 7.4841) -> (-34.4206, 7.4841) projected
  line L259 (-34.4206, 10.2829) -> (-35.2461, 10.2829) projected
  line L260 (-32.6953, 16.553) -> (-34.4206, 16.553) projected
  line L261 (-32.6953, 17.7532) -> (-32.6953, 16.553) projected
  line L262 (-29.3949, 17.7532) -> (-32.6953, 17.7532) projected
  line L263 (-29.3949, 16.553) -> (-29.3949, 17.7532) projected
  line L264 (-27.671, 16.553) -> (-29.3949, 16.553) projected
  line L265 (-8.8952, 16.553) -> (-10.6206, 16.553) projected
  line L266 (-8.8952, 17.7532) -> (-8.8952, 16.553) projected
  line L267 (-5.5948, 17.7532) -> (-8.8952, 17.7532) projected
  line L268 (-5.5948, 16.553) -> (-5.5948, 17.7532) projected
  line L269 (-3.8709, 16.553) -> (-5.5948, 16.553) projected
  line L270 (-3.0441, 10.2829) -> (-3.8709, 10.2829) projected
  line L271 (-3.8709, 7.4841) -> (-3.0441, 7.4841) projected
  dimension "d3" = 38.1
  dimension "d6" = 19.431
  dimension "d7" = 76.2
  dimension "d54" = 19.431
  constraints: 16 end point, 4 parallel, 2 horizontal, 2 perpendicular, 2 point on line
  measures "d3" distance between parallel lines of L3 L1
  measures "d6" distance of L5.end L6.end
  measures "d7" distance of L4.end L5.end
  measures "d54" distance between parallel lines of L2 L51
extrude "Extrusion2" [suppressed]
sketch "Sketch4" plane through (0, 0, 3) normal (0, 0, 1) x (1, 0, 0)
  line L0 (16.6205, 35.8316) -> (16.6205, 21.8323) construction
  line L1 (35.6704, 21.8323) -> (21.671, 21.8323) construction
  line L2 (16.6205, 21.8323) -> (21.671, 21.8323) construction
  line L3 (21.671, 21.8323) -> (19.1457, 21.8323) construction
  line L4 (19.1457, 16.7831) -> (19.1457, 21.8323) construction
  line L5 (54.7204, 35.8316) -> (54.7204, 21.8323) construction
  line L6 (40.7211, 16.7831) -> (54.7204, 16.7831) construction
  line L7 (54.7204, 21.8323) -> (54.7204, 16.7831) construction
  line L8 (54.7204, 16.7831) -> (54.7204, 19.3077) construction
  line L9 (59.7711, 12.3073) -> (59.7711, 26.3067) construction
  line L10 (59.7711, 19.307) -> (54.7204, 19.3077) construction
  line L11 (16.6205, 59.9324) -> (21.671, 54.8816) construction
  line L12 (54.7204, 59.9324) -> (40.7211, 59.9324) construction
  line L13 (21.671, 54.8816) -> (35.6704, 54.8816) construction
  line L14 (35.6704, 59.9324) -> (21.671, 59.9324) construction
  line L15 (35.6704, 112.032) -> (35.6704, 98.0324) construction
  line L16 (2.621, 92.9816) -> (16.6205, 92.9816) construction
  line L17 (21.671, 92.9816) -> (35.6704, 92.9816) construction
  line L18 (73.7704, 98.0324) -> (59.7711, 98.0324) construction
  line L19 (16.6205, 54.8816) -> (16.6205, 40.8824) construction
  line L20 (16.6205, 54.8816) -> (21.671, 59.9324) construction
  line L21 (35.6704, 98.0324) -> (21.671, 98.0324) construction
  line L22 (16.6205, 92.9816) -> (21.671, 98.0324) construction
  line L23 (21.671, 98.0324) -> (21.671, 92.9816) construction
  circle A0 centre (19.1457, 95.507) radius 1
  circle A1 centre (19.1457, 95.507) radius 2
  circle A2 centre (57.2458, 95.507) radius 1
  circle A3 centre (57.2458, 95.507) radius 2
  line L24 (59.7711, 50.4074) -> (59.7711, 64.4066) projected
  line L25 (59.7711, 57.407) -> (54.7204, 57.407) construction
  circle A4 centre (19.1457, 57.407) radius 1
  circle A5 centre (19.1457, 57.407) radius 2
  circle A6 centre (57.2458, 57.407) radius 1
  circle A7 centre (57.2458, 57.407) radius 2
  circle A8 centre (57.2458, 19.3073) radius 1
  circle A9 centre (57.2458, 19.3073) radius 2
  circle A10 centre (19.1457, 19.3077) radius 1
  circle A11 centre (19.1457, 19.3077) radius 2
  line L26 (12.146, 16.7831) -> (26.1455, 16.7831) projected
  line L27 (28.6707, 21.8323) -> (28.6707, 18.3077) construction
  line L28 (35.6704, 35.8316) -> (35.6704, 21.8323) construction
  line L29 (35.6704, 28.832) -> (40.7211, 28.832) construction
  line L30 (40.7211, 21.8323) -> (40.7211, 35.8316) construction
  circle A12 centre (38.1957, 19.3077) radius 1
  circle A13 centre (38.1957, 19.3077) radius 2
  circle A14 centre (38.1957, 38.3562) radius 2
  circle A15 centre (38.1957, 38.3562) radius 1
  line L31 (54.7204, 59.9324) -> (40.7211, 59.9324) construction
  line L32 (47.7208, 59.9324) -> (47.7208, 54.8816) construction
  line L33 (40.7211, 54.8816) -> (54.7204, 54.8816) construction
  circle A16 centre (38.1958, 57.407) radius 1
  circle A17 centre (38.1958, 57.407) radius 2
  line L34 (35.6704, 40.8824) -> (21.671, 40.8824) construction
  line L35 (28.6707, 40.8824) -> (28.6707, 35.8316) construction
  line L36 (21.671, 35.8316) -> (35.6704, 35.8316) construction
  circle A18 centre (19.1457, 38.3562) radius 2
  circle A19 centre (19.1457, 38.3562) radius 1
  point P0 (0, 0)
  dimension "d8" = 2
  dimension "d9" = 4
  dimension "d12" = 2
  dimension "d13" = 4
  dimension "d14" = 2
  dimension "d15" = 4
  dimension "d16" = 2
  dimension "d17" = 4
  dimension "d18" = 2
  dimension "d19" = 4
  dimension "d22" = 2
  dimension "d23" = 4
  constraints: 30 end point, 20 centre point, 17 midpoint, 11 coincident, 8 symmetric about line, 3 vertical, 2 vertical alignment, 1 collinear, 1 horizontal, 1 horizontal alignment, 8 other
  measures "d8" diameter of A0
  measures "d9" diameter of A1
  measures "d12" diameter of A2
  measures "d13" diameter of A3
  measures "d14" diameter of A4
  measures "d15" diameter of A5
  measures "d16" diameter of A6
  measures "d17" diameter of A7
  measures "d18" diameter of A8
  measures "d19" diameter of A9
  measures "d22" diameter of A10
  measures "d23" diameter of A11
extrude "Extrusion4" cut sketch "Sketch4" against normal blind 3 contours A0 | A2 | A12 | A16
sketch "r" plane through (0, 0, 0) normal (0, 0, -1) x (-1, 0, 0)
  circle A0 centre (-57.2458, 95.507) radius 1 projected
  circle A1 centre (-19.1457, 95.507) radius 1 projected
  line L0 (-0.0951, 111.558) -> (-0.0951, 3.2577) projected
  line L1 (-0.1047, 111.794) -> (-0.0951, 111.558) projected
  line L2 (-0.1309, 112.028) -> (-0.1047, 111.794) projected
  line L3 (-0.1778, 112.258) -> (-0.1309, 112.028) projected
  line L4 (-0.2412, 112.485) -> (-0.1778, 112.258) projected
  line L5 (-0.3238, 112.705) -> (-0.2412, 112.485) projected
  line L6 (-0.4217, 112.919) -> (-0.3238, 112.705) projected
  line L7 (-0.5374, 113.126) -> (-0.4217, 112.919) projected
  line L8 (-0.667, 113.322) -> (-0.5374, 113.126) projected
  line L9 (-0.813, 113.506) -> (-0.667, 113.322) projected
  line L10 (-0.9729, 113.68) -> (-0.813, 113.506) projected
  line L11 (-1.1465, 113.84) -> (-0.9729, 113.68) projected
  line L12 (-1.3312, 113.986) -> (-1.1465, 113.84) projected
  line L13 (-1.5269, 114.115) -> (-1.3312, 113.986) projected
  line L14 (-1.7336, 114.231) -> (-1.5269, 114.115) projected
  line L15 (-1.9472, 114.329) -> (-1.7336, 114.231) projected
  line L16 (-2.1677, 114.411) -> (-1.9472, 114.329) projected
  line L17 (-2.395, 114.475) -> (-2.1677, 114.411) projected
  line L18 (-2.6252, 114.522) -> (-2.395, 114.475) projected
  line L19 (-2.8594, 114.548) -> (-2.6252, 114.522) projected
  line L20 (-3.0951, 114.558) -> (-2.8594, 114.548) projected
  line L21 (-73.2966, 114.558) -> (-3.0951, 114.558) projected
  line L22 (-73.5323, 114.548) -> (-73.2966, 114.558) projected
  line L23 (-73.7651, 114.522) -> (-73.5323, 114.548) projected
  line L24 (-73.9965, 114.475) -> (-73.7651, 114.522) projected
  line L25 (-74.2237, 114.411) -> (-73.9965, 114.475) projected
  line L26 (-74.4442, 114.329) -> (-74.2237, 114.411) projected
  line L27 (-74.658, 114.231) -> (-74.4442, 114.329) projected
  line L28 (-74.8633, 114.115) -> (-74.658, 114.231) projected
  line L29 (-75.0591, 113.986) -> (-74.8633, 114.115) projected
  line L30 (-75.245, 113.84) -> (-75.0591, 113.986) projected
  line L31 (-75.4172, 113.68) -> (-75.245, 113.84) projected
  line L32 (-75.577, 113.506) -> (-75.4172, 113.68) projected
  line L33 (-75.723, 113.322) -> (-75.577, 113.506) projected
  line L34 (-75.8543, 113.126) -> (-75.723, 113.322) projected
  line L35 (-75.97, 112.919) -> (-75.8543, 113.126) projected
  line L36 (-76.0677, 112.705) -> (-75.97, 112.919) projected
  line L37 (-76.1488, 112.485) -> (-76.0677, 112.705) projected
  line L38 (-76.2138, 112.258) -> (-76.1488, 112.485) projected
  line L39 (-76.2593, 112.028) -> (-76.2138, 112.258) projected
  line L40 (-76.2868, 111.794) -> (-76.2593, 112.028) projected
  line L41 (-76.2963, 111.558) -> (-76.2868, 111.794) projected
  line L42 (-76.2963, 3.2563) -> (-76.2963, 111.558) projected
  line L43 (-3.0951, 0.2563) -> (-73.2952, 0.2563) projected
  line L44 (-40.7211, 16.7831) -> (-54.7204, 16.7831) projected
  line L45 (-40.7211, 2.7836) -> (-40.7211, 16.7831) projected
  line L46 (-54.7204, 2.7836) -> (-40.7211, 2.7836) projected
  line L47 (-54.7204, 16.7831) -> (-54.7204, 2.7836) projected
  line L48 (-2.621, 35.8316) -> (-16.6205, 35.8316) projected
  line L49 (-2.621, 21.8323) -> (-2.621, 35.8316) projected
  line L50 (-16.6205, 21.8323) -> (-2.621, 21.8323) projected
  line L51 (-16.6205, 35.8316) -> (-16.6205, 21.8323) projected
  line L52 (-21.671, 35.8316) -> (-35.6704, 35.8316) projected
  line L53 (-21.671, 21.8323) -> (-21.671, 35.8316) projected
  line L54 (-35.6704, 21.8323) -> (-21.671, 21.8323) projected
  line L55 (-35.6704, 35.8316) -> (-35.6704, 21.8323) projected
  line L56 (-40.7211, 35.8316) -> (-54.7204, 35.8316) projected
  line L57 (-40.7211, 21.8323) -> (-40.7211, 35.8316) projected
  line L58 (-54.7204, 21.8323) -> (-40.7211, 21.8323) projected
  line L59 (-54.7204, 35.8316) -> (-54.7204, 21.8323) projected
  line L60 (-2.621, 54.8816) -> (-16.6205, 54.8816) projected
  line L61 (-2.621, 40.8824) -> (-2.621, 54.8816) projected
  line L62 (-16.6205, 40.8824) -> (-2.621, 40.8824) projected
  line L63 (-16.6205, 54.8816) -> (-16.6205, 40.8824) projected
  line L64 (-21.671, 54.8816) -> (-35.6704, 54.8816) projected
  line L65 (-21.671, 40.8824) -> (-21.671, 54.8816) projected
  line L66 (-35.6704, 40.8824) -> (-21.671, 40.8824) projected
  line L67 (-35.6704, 54.8816) -> (-35.6704, 40.8824) projected
  line L68 (-40.7211, 54.8816) -> (-54.7204, 54.8816) projected
  line L69 (-40.7211, 40.8824) -> (-40.7211, 54.8816) projected
  line L70 (-54.7204, 40.8824) -> (-40.7211, 40.8824) projected
  line L71 (-54.7204, 54.8816) -> (-54.7204, 40.8824) projected
  line L72 (-2.621, 73.9316) -> (-16.6205, 73.9316) projected
  line L73 (-2.621, 59.9324) -> (-2.621, 73.9316) projected
  line L74 (-16.6205, 59.9324) -> (-2.621, 59.9324) projected
  line L75 (-16.6205, 73.9316) -> (-16.6205, 59.9324) projected
  line L76 (-21.671, 73.9316) -> (-35.6704, 73.9316) projected
  line L77 (-21.671, 59.9324) -> (-21.671, 73.9316) projected
  line L78 (-35.6704, 59.9324) -> (-21.671, 59.9324) projected
  line L79 (-35.6704, 73.9316) -> (-35.6704, 59.9324) projected
  line L80 (-40.7211, 73.9316) -> (-54.7204, 73.9316) projected
  line L81 (-40.7211, 59.9324) -> (-40.7211, 73.9316) projected
  line L82 (-54.7204, 59.9324) -> (-40.7211, 59.9324) projected
  line L83 (-54.7204, 73.9316) -> (-54.7204, 59.9324) projected
  line L84 (-2.621, 92.9816) -> (-16.6205, 92.9816) projected
  line L85 (-2.621, 78.9824) -> (-2.621, 92.9816) projected
  line L86 (-16.6205, 78.9824) -> (-2.621, 78.9824) projected
  line L87 (-16.6205, 92.9816) -> (-16.6205, 78.9824) projected
  line L88 (-21.671, 92.9816) -> (-35.6704, 92.9816) projected
  line L89 (-21.671, 78.9824) -> (-21.671, 92.9816) projected
  line L90 (-35.6704, 78.9824) -> (-21.671, 78.9824) projected
  line L91 (-35.6704, 92.9816) -> (-35.6704, 78.9824) projected
  line L92 (-40.7211, 92.9816) -> (-54.7204, 92.9816) projected
  line L93 (-40.7211, 78.9824) -> (-40.7211, 92.9816) projected
  line L94 (-54.7204, 78.9824) -> (-40.7211, 78.9824) projected
  line L95 (-54.7204, 92.9816) -> (-54.7204, 78.9824) projected
  line L96 (-59.7711, 92.9816) -> (-73.7704, 92.9816) projected
  line L97 (-59.7711, 78.9824) -> (-59.7711, 92.9816) projected
  line L98 (-73.7704, 78.9824) -> (-59.7711, 78.9824) projected
  line L99 (-73.7704, 92.9816) -> (-73.7704, 78.9824) projected
  line L100 (-2.621, 112.032) -> (-16.6205, 112.032) projected
  line L101 (-2.621, 98.0324) -> (-2.621, 112.032) projected
  line L102 (-16.6205, 98.0324) -> (-2.621, 98.0324) projected
  line L103 (-16.6205, 112.032) -> (-16.6205, 98.0324) projected
  line L104 (-21.671, 112.032) -> (-35.6704, 112.032) projected
  line L105 (-21.671, 98.0324) -> (-21.671, 112.032) projected
  line L106 (-35.6704, 98.0324) -> (-21.671, 98.0324) projected
  line L107 (-35.6704, 112.032) -> (-35.6704, 98.0324) projected
  line L108 (-40.7211, 112.032) -> (-54.7204, 112.032) projected
  line L109 (-40.7211, 98.0324) -> (-40.7211, 112.032) projected
  line L110 (-54.7204, 98.0324) -> (-40.7211, 98.0324) projected
  line L111 (-54.7204, 112.032) -> (-54.7204, 98.0324) projected
  line L112 (-59.7711, 112.032) -> (-73.7704, 112.032) projected
  line L113 (-59.7711, 98.0324) -> (-59.7711, 112.032) projected
  line L114 (-73.7704, 98.0324) -> (-59.7711, 98.0324) projected
  line L115 (-73.7704, 112.032) -> (-73.7704, 98.0324) projected
  line L116 (-58.7711, 97.0324) -> (-58.7711, 113.032)
  line L117 (-58.7711, 113.032) -> (-74.7704, 113.032)
  line L118 (-74.7704, 113.032) -> (-74.7704, 97.0324)
  line L119 (-74.7704, 97.0324) -> (-58.7711, 97.0324)
  line L120 (-58.7711, 113.032) -> (-74.7704, 97.0324) construction
  line L121 (-58.7711, 97.0324) -> (-74.7704, 113.032) construction
  line L122 (-66.7708, 105.0322) -> (-52.9583, 105.0322) construction
  line L123 (-66.7708, 105.0322) -> (-66.7708, 100.7955) construction
  line L124 (-39.7211, 97.0324) -> (-39.7211, 113.032)
  line L125 (-39.7211, 113.032) -> (-55.7204, 113.032)
  line L126 (-55.7204, 113.032) -> (-55.7204, 97.0324)
  line L127 (-55.7204, 97.0324) -> (-39.7211, 97.0324)
  line L128 (-20.6711, 97.0324) -> (-20.6711, 113.032)
  line L129 (-20.6711, 113.032) -> (-36.6704, 113.032)
  line L130 (-36.6704, 113.032) -> (-36.6704, 97.0324)
  line L131 (-36.6704, 97.0324) -> (-20.6711, 97.0324)
  line L132 (-1.6211, 97.0324) -> (-1.6211, 113.032)
  line L133 (-1.6211, 113.032) -> (-17.6204, 113.032)
  line L134 (-17.6204, 113.032) -> (-17.6204, 97.0324)
  line L135 (-17.6204, 97.0324) -> (-1.6211, 97.0324)
  line L136 (-58.7711, 77.9824) -> (-58.7711, 93.982)
  line L137 (-58.7711, 93.982) -> (-74.7704, 93.982)
  line L138 (-74.7704, 93.982) -> (-74.7704, 77.9824)
  line L139 (-74.7704, 77.9824) -> (-58.7711, 77.9824)
  line L140 (-39.7211, 77.9824) -> (-39.7211, 93.982)
  line L141 (-39.7211, 93.982) -> (-55.7204, 93.982)
  line L142 (-55.7204, 93.982) -> (-55.7204, 77.9824)
  line L143 (-55.7204, 77.9824) -> (-39.7211, 77.9824)
  line L144 (-20.6711, 77.9824) -> (-20.6711, 93.982)
  line L145 (-20.6711, 93.982) -> (-36.6704, 93.982)
  line L146 (-36.6704, 93.982) -> (-36.6704, 77.9824)
  line L147 (-36.6704, 77.9824) -> (-20.6711, 77.9824)
  line L148 (-1.6211, 77.9824) -> (-1.6211, 93.982)
  line L149 (-1.6211, 93.982) -> (-17.6204, 93.982)
  line L150 (-17.6204, 93.982) -> (-17.6204, 77.9824)
  line L151 (-17.6204, 77.9824) -> (-1.6211, 77.9824)
  line L152 (-58.7711, 58.9324) -> (-58.7711, 74.932)
  line L153 (-58.7711, 74.932) -> (-74.7704, 74.932)
  line L154 (-74.7704, 74.932) -> (-74.7704, 58.9324)
  line L155 (-74.7704, 58.9324) -> (-58.7711, 58.9324)
  line L156 (-39.7211, 58.9324) -> (-39.7211, 74.932)
  line L157 (-39.7211, 74.932) -> (-55.7204, 74.932)
  line L158 (-55.7204, 74.932) -> (-55.7204, 58.9324)
  line L159 (-55.7204, 58.9324) -> (-39.7211, 58.9324)
  line L160 (-20.6711, 58.9324) -> (-20.6711, 74.932)
  line L161 (-20.6711, 74.932) -> (-36.6704, 74.932)
  line L162 (-36.6704, 74.932) -> (-36.6704, 58.9324)
  line L163 (-36.6704, 58.9324) -> (-20.6711, 58.9324)
  line L164 (-1.6211, 58.9324) -> (-1.6211, 74.932)
  line L165 (-1.6211, 74.932) -> (-17.6204, 74.932)
  line L166 (-17.6204, 74.932) -> (-17.6204, 58.9324)
  line L167 (-17.6204, 58.9324) -> (-1.6211, 58.9324)
  line L168 (-58.7711, 39.8824) -> (-58.7711, 55.882)
  line L169 (-58.7711, 55.882) -> (-74.7704, 55.882)
  line L170 (-74.7704, 55.882) -> (-74.7704, 39.8824)
  line L171 (-74.7704, 39.8824) -> (-58.7711, 39.8824)
  line L172 (-39.7211, 39.8824) -> (-39.7211, 55.882)
  line L173 (-39.7211, 55.882) -> (-55.7204, 55.882)
  line L174 (-55.7204, 55.882) -> (-55.7204, 39.8824)
  line L175 (-55.7204, 39.8824) -> (-39.7211, 39.8824)
  line L176 (-20.6711, 39.8824) -> (-20.6711, 55.882)
  line L177 (-20.6711, 55.882) -> (-36.6704, 55.882)
  line L178 (-36.6704, 55.882) -> (-36.6704, 39.8824)
  line L179 (-36.6704, 39.8824) -> (-20.6711, 39.8824)
  line L180 (-1.6211, 39.8824) -> (-1.6211, 55.882)
  line L181 (-1.6211, 55.882) -> (-17.6204, 55.882)
  line L182 (-17.6204, 55.882) -> (-17.6204, 39.8824)
  line L183 (-17.6204, 39.8824) -> (-1.6211, 39.8824)
  line L184 (-58.7711, 20.8324) -> (-58.7711, 36.832)
  line L185 (-58.7711, 36.832) -> (-74.7704, 36.832)
  line L186 (-74.7704, 36.832) -> (-74.7704, 20.8324)
  line L187 (-74.7704, 20.8324) -> (-58.7711, 20.8324)
  line L188 (-39.7211, 20.8324) -> (-39.7211, 36.832)
  line L189 (-39.7211, 36.832) -> (-55.7204, 36.832)
  line L190 (-55.7204, 36.832) -> (-55.7204, 20.8324)
  line L191 (-55.7204, 20.8324) -> (-39.7211, 20.8324)
  line L192 (-20.6711, 20.8324) -> (-20.6711, 36.832)
  line L193 (-20.6711, 36.832) -> (-36.6704, 36.832)
  line L194 (-36.6704, 36.832) -> (-36.6704, 20.8324)
  line L195 (-36.6704, 20.8324) -> (-20.6711, 20.8324)
  line L196 (-1.6211, 20.8324) -> (-1.6211, 36.832)
  line L197 (-1.6211, 36.832) -> (-17.6204, 36.832)
  line L198 (-17.6204, 36.832) -> (-17.6204, 20.8324)
  line L199 (-17.6204, 20.8324) -> (-1.6211, 20.8324)
  line L200 (-58.7711, 1.7824) -> (-58.7711, 17.782)
  line L201 (-58.7711, 17.782) -> (-74.7704, 17.782)
  line L202 (-74.7704, 17.782) -> (-74.7704, 1.7824)
  line L203 (-74.7704, 1.7824) -> (-58.7711, 1.7824)
  line L204 (-39.7211, 1.7824) -> (-39.7211, 17.782)
  line L205 (-39.7211, 17.782) -> (-55.7204, 17.782)
  line L206 (-55.7204, 17.782) -> (-55.7204, 1.7824)
  line L207 (-55.7204, 1.7824) -> (-39.7211, 1.7824)
  line L208 (-20.6711, 1.7824) -> (-20.6711, 17.782)
  line L209 (-20.6711, 17.782) -> (-36.6704, 17.782)
  line L210 (-36.6704, 17.782) -> (-36.6704, 1.7824)
  line L211 (-36.6704, 1.7824) -> (-20.6711, 1.7824)
  line L212 (-1.6211, 1.7824) -> (-1.6211, 17.782)
  line L213 (-1.6211, 17.782) -> (-17.6204, 17.782)
  line L214 (-17.6204, 17.782) -> (-17.6204, 1.7824)
  line L215 (-17.6204, 1.7824) -> (-1.6211, 1.7824)
  line L216 (-76.2868, 3.0207) -> (-76.2963, 3.2563) projected
  line L217 (-76.2593, 2.7878) -> (-76.2868, 3.0207) projected
  line L218 (-76.2138, 2.5563) -> (-76.2593, 2.7878) projected
  line L219 (-76.1488, 2.3289) -> (-76.2138, 2.5563) projected
  line L220 (-76.0677, 2.1084) -> (-76.1488, 2.3289) projected
  line L221 (-75.97, 1.8948) -> (-76.0677, 2.1084) projected
  line L222 (-75.8543, 1.6895) -> (-75.97, 1.8948) projected
  line L223 (-75.723, 1.4938) -> (-75.8543, 1.6895) projected
  line L224 (-75.577, 1.3078) -> (-75.723, 1.4938) projected
  line L225 (-75.4172, 1.1355) -> (-75.577, 1.3078) projected
  line L226 (-75.245, 0.9757) -> (-75.4172, 1.1355) projected
  line L227 (-75.0591, 0.8296) -> (-75.245, 0.9757) projected
  line L228 (-74.8633, 0.6987) -> (-75.0591, 0.8296) projected
  line L229 (-74.658, 0.5829) -> (-74.8633, 0.6987) projected
  line L230 (-74.4442, 0.4851) -> (-74.658, 0.5829) projected
  line L231 (-74.2237, 0.4038) -> (-74.4442, 0.4851) projected
  line L232 (-73.9965, 0.339) -> (-74.2237, 0.4038) projected
  line L233 (-73.7651, 0.2935) -> (-73.9965, 0.339) projected
  line L234 (-73.5323, 0.266) -> (-73.7651, 0.2935) projected
  line L235 (-73.2952, 0.2563) -> (-73.5323, 0.266) projected
  line L236 (-2.8594, 0.266) -> (-3.0951, 0.2563) projected
  line L237 (-2.6252, 0.2935) -> (-2.8594, 0.266) projected
  line L238 (-2.395, 0.339) -> (-2.6252, 0.2935) projected
  line L239 (-2.1677, 0.4038) -> (-2.395, 0.339) projected
  line L240 (-1.9472, 0.4851) -> (-2.1677, 0.4038) projected
  line L241 (-1.7336, 0.5829) -> (-1.9472, 0.4851) projected
  line L242 (-1.5269, 0.6987) -> (-1.7336, 0.5829) projected
  line L243 (-1.3312, 0.8296) -> (-1.5269, 0.6987) projected
  line L244 (-1.1465, 0.9757) -> (-1.3312, 0.8296) projected
  line L245 (-0.9729, 1.1355) -> (-1.1465, 0.9757) projected
  line L246 (-0.813, 1.3078) -> (-0.9729, 1.1355) projected
  line L247 (-0.667, 1.4938) -> (-0.813, 1.3078) projected
  line L248 (-0.5374, 1.6895) -> (-0.667, 1.4938) projected
  line L249 (-0.4217, 1.8948) -> (-0.5374, 1.6895) projected
  line L250 (-0.3238, 2.1084) -> (-0.4217, 1.8948) projected
  line L251 (-0.2412, 2.3289) -> (-0.3238, 2.1084) projected
  line L252 (-0.1778, 2.5563) -> (-0.2412, 2.3289) projected
  line L253 (-0.1309, 2.7878) -> (-0.1778, 2.5563) projected
  line L254 (-0.1047, 3.0207) -> (-0.1309, 2.7878) projected
  line L255 (-0.0951, 3.2577) -> (-0.1047, 3.0207) projected
  point P0 (0, 0)
  dimension "d29" = 1
  dimension "d32" = 19.05
  dimension "d35" = 19.05
  constraints: 200 end point, 2 horizontal, 2 vertical, 1 midpoint, 187 other
  measures "d29" distance between parallel lines of L114 L119
  measures "d32" distance of L116.start L124.start
  measures "d35" distance of L116.start L136.start